Autodesk Fusion 360 part; units mm, degrees
(part 2 of 2)
sketch "Logo 2" plane through (0, 0, 64.4928) normal (0, 0, 1) x (1, 0, 0)
  line L0 (33.9049, -0.8564) -> (38.2716, 2.693)
  spline S0 degree 5 poles (38.2716, 2.693) (38.2649, 2.6875) (38.2517, 2.6763) (38.232, 2.6595) (38.206, 2.6368) (38.1742, 2.6081) (38.1429, 2.579) (38.1122, 2.5495) (38.082, 2.5196) (38.0525, 2.4893) (38.0235, 2.4586) (37.9952, 2.4275) (37.9674, 2.396) (37.9403, 2.3641) (37.9138, 2.3318) (37.8879, 2.2991) (37.8627, 2.266) (37.8381, 2.2325) (37.8142, 2.1986) (37.791, 2.1644) (37.7684, 2.1298) (37.7464, 2.0948) (37.7252, 2.0595) (37.7046, 2.0238) (37.6847, 1.9877) (37.6655, 1.9513) (37.6469, 1.9145) (37.6291, 1.8774) (37.6119, 1.8399) (37.5955, 1.8021) (37.5797, 1.764) (37.5646, 1.7256) (37.5502, 1.6868) (37.5365, 1.6478) (37.5236, 1.6084) (37.5113, 1.5687) (37.4997, 1.5288) (37.4888, 1.4885) (37.4786, 1.448) (37.4691, 1.4072) (37.4603, 1.3662) (37.4521, 1.3249) (37.4447, 1.2834) (37.4379, 1.2416) (37.4318, 1.1996) (37.4264, 1.1573) (37.4216, 1.1148) (37.4175, 1.0721) (37.414, 1.0292) (37.4112, 0.9861) (37.409, 0.9428) (37.4075, 0.8993) (37.4066, 0.8556) (37.4064, 0.8117) (37.4068, 0.7676) (37.4078, 0.7234) (37.4094, 0.6789) (37.4116, 0.6344) (37.4144, 0.5896) (37.4178, 0.5447) (37.4218, 0.4997) (37.4264, 0.4545) (37.4316, 0.4092) (37.4373, 0.3637) (37.4436, 0.3181) (37.4505, 0.2723) (37.4579, 0.2264) (37.4658, 0.1804) (37.4743, 0.1343) (37.4833, 0.088) (37.4929, 0.0416) (37.503, -0.0049) (37.5135, -0.0515) (37.5246, -0.0982) (37.5363, -0.145) (37.5484, -0.1919) (37.561, -0.239) (37.574, -0.2861) (37.5876, -0.3333) (37.6017, -0.3806) (37.6162, -0.428) (37.6312, -0.4755) (37.6467, -0.5231) (37.6626, -0.5708) (37.6789, -0.6186) (37.6957, -0.6665) (37.7129, -0.7144) (37.7306, -0.7625) (37.7487, -0.8106) (37.7672, -0.8588) (37.7861, -0.907) (37.8055, -0.9554) (37.8253, -1.0038) (37.8455, -1.0523) (37.8661, -1.1008) (37.8871, -1.1495) (37.9085, -1.1982) (37.9303, -1.247) (37.9524, -1.2958) (37.975, -1.3447) (37.9979, -1.3937) (38.0213, -1.4428) (38.045, -1.4919) (38.069, -1.5411) (38.0934, -1.5903) (38.1182, -1.6396) (38.1433, -1.689) (38.1688, -1.7384) (38.1946, -1.7879) (38.2208, -1.8375) (38.2474, -1.8871) (38.2742, -1.9368) (38.3014, -1.9865) (38.329, -2.0363) (38.3569, -2.0862) (38.3851, -2.1361) (38.4136, -2.186) (38.4425, -2.2361) (38.4716, -2.2861) (38.5011, -2.3363) (38.531, -2.3864) (38.5611, -2.4367) (38.5915, -2.487) (38.6223, -2.5373) (38.6533, -2.5877) (38.6847, -2.6382) (38.7163, -2.6887) (38.7482, -2.7392) (38.7805, -2.7898) (38.813, -2.8405) (38.8458, -2.8912) (38.8789, -2.942) (38.9122, -2.9929) (38.9459, -3.0437) (38.9798, -3.0947) (39.014, -3.1456) (39.0485, -3.1966) (39.0833, -3.2476) (39.1184, -3.2987) (39.1538, -3.3498) (39.1894, -3.401) (39.2252, -3.4523) (39.2613, -3.5036) (39.2976, -3.555) (39.3341, -3.6066) (39.3709, -3.6581) (39.408, -3.7096) (39.4454, -3.7612) (39.4832, -3.8126) (39.5213, -3.864) (39.5597, -3.9155) (39.5984, -3.967) (39.6371, -4.0186) (39.676, -4.0705) (39.7148, -4.1226) (39.7536, -4.175) (39.7926, -4.2276) (39.8318, -4.2802) (39.8714, -4.3327) (39.9118, -4.3848) (39.9529, -4.4363) (39.9951, -4.4872) (40.0382, -4.5373) (40.0822, -4.5866) (40.1268, -4.6353) (40.1719, -4.6834) (40.2173, -4.7312) (40.2625, -4.7788) (40.3076, -4.8263) (40.3524, -4.8736) (40.3969, -4.921) (40.4413, -4.9681) (40.4855, -5.0152) (40.5297, -5.0619) (40.574, -5.1084) (40.6185, -5.1546) (40.663, -5.2004) (40.7076, -5.2459) (40.7523, -5.2911) (40.7971, -5.3361) (40.8417, -5.3808) (40.8864, -5.4253) (40.931, -5.4695) (40.9756, -5.5135) (41.0201, -5.5572) (41.0647, -5.6006) (41.1093, -5.6438) (41.1539, -5.6867) (41.1986, -5.7293) (41.2432, -5.7716) (41.2879, -5.8136) (41.3326, -5.8554) (41.3773, -5.8968) (41.422, -5.938) (41.4667, -5.9789) (41.5114, -6.0195) (41.5561, -6.0598) (41.6008, -6.0997) (41.6455, -6.1394) (41.6903, -6.1788) (41.735, -6.2179) (41.7798, -6.2567) (41.8245, -6.2951) (41.8693, -6.3333) (41.9141, -6.3711) (41.9589, -6.4087) (42.0037, -6.4459) (42.0485, -6.4827) (42.0933, -6.5193) (42.1381, -6.5555) (42.183, -6.5914) (42.2278, -6.6269) (42.2727, -6.6621) (42.3176, -6.6969) (42.3624, -6.7315) (42.4073, -6.7656) (42.4522, -6.7994) (42.4971, -6.8329) (42.5421, -6.866) (42.587, -6.8988) (42.6319, -6.9312) (42.6769, -6.9632) (42.7218, -6.9948) (42.7668, -7.0261) (42.8118, -7.057) (42.8567, -7.0875) (42.9017, -7.1176) (42.9467, -7.1473) (42.9917, -7.1766) (43.0367, -7.2056) (43.0817, -7.2341) (43.1267, -7.2623) (43.1718, -7.29) (43.2168, -7.3173) (43.2619, -7.3442) (43.3069, -7.3707) (43.352, -7.3967) (43.397, -7.4223) (43.4421, -7.4475) (43.4872, -7.4722) (43.5322, -7.4965) (43.5773, -7.5203) (43.6223, -7.5437) (43.6674, -7.5666) (43.7125, -7.5891) (43.7575, -7.6111) (43.8026, -7.6326) (43.8477, -7.6536) (43.8927, -7.6741) (43.9378, -7.6942) (43.9828, -7.7138) (44.0279, -7.7328) (44.0729, -7.7514) (44.1179, -7.7695) (44.1629, -7.787) (44.2079, -7.804) (44.2528, -7.8205) (44.2978, -7.8364) (44.3427, -7.8518) (44.3876, -7.8666) (44.4325, -7.8809) (44.4774, -7.8946) (44.5222, -7.9078) (44.567, -7.9204) (44.6118, -7.9325) (44.6566, -7.9439) (44.7013, -7.9548) (44.7459, -7.965) (44.7905, -7.9747) (44.8351, -7.9838) (44.8796, -7.9922) (44.9241, -8.0001) (44.9685, -8.0073) (45.0129, -8.0139) (45.0572, -8.0198) (45.1014, -8.0251) (45.1455, -8.0298) (45.1896, -8.0338) (45.2336, -8.0372) (45.2775, -8.04) (45.3213, -8.042) (45.365, -8.0434) (45.4086, -8.0442) (45.4521, -8.0443) (45.4955, -8.0437) (45.5388, -8.0424) (45.582, -8.0404) (45.6251, -8.0377) (45.668, -8.0343) (45.7108, -8.0303) (45.7534, -8.0256) (45.7959, -8.0201) (45.8383, -8.014) (45.8805, -8.0071) (45.9226, -7.9996) (45.9645, -7.9914) (46.0062, -7.9824) (46.0477, -7.9728) (46.089, -7.9624) (46.1302, -7.9514) (46.1712, -7.9397) (46.2119, -7.9273) (46.2525, -7.9142) (46.2929, -7.9004) (46.333, -7.8859) (46.373, -7.8707) (46.4127, -7.8549) (46.4522, -7.8383) (46.4915, -7.8211) (46.5305, -7.8032) (46.5693, -7.7847) (46.6079, -7.7655) (46.6462, -7.7456) (46.6843, -7.7251) (46.7221, -7.7039) (46.7597, -7.6821) (46.797, -7.6597) (46.8341, -7.6366) (46.8709, -7.6129) (46.9074, -7.5886) (46.9437, -7.5636) (46.9726, -7.5432) (46.9941, -7.5276) (47.0084, -7.5171) (47.0155, -7.5118) knots 0 0 0 0 0 0 0.003125 0.00625 0.009375 0.0125 0.015625 0.01875 0.021875 0.025 0.028125 0.03125 0.034375 0.0375 0.040625 0.04375 0.046875 0.05 0.053125 0.05625 0.059375 0.0625 0.065625 0.06875 0.071875 0.075 0.078125 0.08125 0.084375 0.0875 0.090625 0.09375 0.096875 0.1 0.103125 0.10625 0.109375 0.1125 0.115625 0.11875 0.121875 0.125 0.128125 0.13125 0.134375 0.1375 0.140625 0.14375 0.146875 0.15 0.153125 0.15625 0.159375 0.1625 0.165625 0.16875 0.171875 0.175 0.178125 0.18125 0.184375 0.1875 0.190625 0.19375 0.196875 0.2 0.203125 0.20625 0.209375 0.2125 0.215625 0.21875 0.221875 0.225 0.228125 0.23125 0.234375 0.2375 0.240625 0.24375 0.246875 0.25 0.253125 0.25625 0.259375 0.2625 0.265625 0.26875 0.271875 0.275 0.278125 0.28125 0.284375 0.2875 0.290625 0.29375 0.296875 0.3 0.303125 0.30625 0.309375 0.3125 0.315625 0.31875 0.321875 0.325 0.328125 0.33125 0.334375 0.3375 0.340625 0.34375 0.346875 0.35 0.353125 0.35625 0.359375 0.3625 0.365625 0.36875 0.371875 0.375 0.378125 0.38125 0.384375 0.3875 0.390625 0.39375 0.396875 0.4 0.403125 0.40625 0.409375 0.4125 0.415625 0.41875 0.421875 0.425 0.428125 0.43125 0.434375 0.4375 0.440625 0.44375 0.446875 0.45 0.453125 0.45625 0.459375 0.4625 0.465625 0.46875 0.471875 0.475 0.478125 0.48125 0.484375 0.4875 0.490625 0.49375 0.496875 0.5 0.503125 0.50625 0.509375 0.5125 0.515625 0.51875 0.521875 0.525 0.528125 0.53125 0.534375 0.5375 0.540625 0.54375 0.546875 0.55 0.553125 0.55625 0.559375 0.5625 0.565625 0.56875 0.571875 0.575 0.578125 0.58125 0.584375 0.5875 0.590625 0.59375 0.596875 0.6 0.603125 0.60625 0.609375 0.6125 0.615625 0.61875 0.621875 0.625 0.628125 0.63125 0.634375 0.6375 0.640625 0.64375 0.646875 0.65 0.653125 0.65625 0.659375 0.6625 0.665625 0.66875 0.671875 0.675 0.678125 0.68125 0.684375 0.6875 0.690625 0.69375 0.696875 0.7 0.703125 0.70625 0.709375 0.7125 0.715625 0.71875 0.721875 0.725 0.728125 0.73125 0.734375 0.7375 0.740625 0.74375 0.746875 0.75 0.753125 0.75625 0.759375 0.7625 0.765625 0.76875 0.771875 0.775 0.778125 0.78125 0.784375 0.7875 0.790625 0.79375 0.796875 0.8 0.803125 0.80625 0.809375 0.8125 0.815625 0.81875 0.821875 0.825 0.828125 0.83125 0.834375 0.8375 0.840625 0.84375 0.846875 0.85 0.853125 0.85625 0.859375 0.8625 0.865625 0.86875 0.871875 0.875 0.878125 0.88125 0.884375 0.8875 0.890625 0.89375 0.896875 0.9 0.903125 0.90625 0.909375 0.9125 0.915625 0.91875 0.921875 0.925 0.928125 0.93125 0.934375 0.9375 0.940625 0.94375 0.946875 0.95 0.953125 0.95625 0.959375 0.9625 0.965625 0.96875 0.971875 0.975 0.978125 0.98125 0.984375 0.9875 0.990625 0.99375 0.996875 1 1 1 1 1 1
  line L1 (47.0155, -7.5118) -> (42.7359, -11.0673)
  spline S1 degree 5 poles (42.7359, -11.0673) (42.7287, -11.0714) (42.7142, -11.0797) (42.6924, -11.0918) (42.6632, -11.1077) (42.6265, -11.127) (42.5896, -11.1457) (42.5526, -11.1639) (42.5153, -11.1815) (42.4779, -11.1985) (42.4403, -11.215) (42.4025, -11.2309) (42.3646, -11.2463) (42.3264, -11.261) (42.2881, -11.2752) (42.2497, -11.2888) (42.211, -11.3018) (42.1722, -11.3143) (42.1332, -11.3261) (42.0941, -11.3374) (42.0549, -11.348) (42.0155, -11.3581) (41.9759, -11.3676) (41.9363, -11.3765) (41.8965, -11.3848) (41.8565, -11.3924) (41.8164, -11.3995) (41.7762, -11.406) (41.7359, -11.4119) (41.6955, -11.4171) (41.655, -11.4218) (41.6143, -11.4259) (41.5735, -11.4294) (41.5327, -11.4324) (41.4917, -11.4347) (41.4507, -11.4364) (41.4095, -11.4376) (41.3683, -11.4381) (41.327, -11.4381) (41.2856, -11.4375) (41.2442, -11.4364) (41.2027, -11.4346) (41.1611, -11.4323) (41.1194, -11.4294) (41.0777, -11.4259) (41.0359, -11.4218) (40.9941, -11.4172) (40.9523, -11.4121) (40.9104, -11.4064) (40.8684, -11.4001) (40.8264, -11.3933) (40.7844, -11.386) (40.7423, -11.3781) (40.7002, -11.3697) (40.658, -11.3608) (40.6159, -11.3513) (40.5737, -11.3413) (40.5315, -11.3308) (40.4893, -11.3198) (40.447, -11.3083) (40.4048, -11.2962) (40.3625, -11.2837) (40.3202, -11.2707) (40.2779, -11.2572) (40.2356, -11.2432) (40.1933, -11.2287) (40.1509, -11.2138) (40.1086, -11.1984) (40.0663, -11.1825) (40.024, -11.1661) (39.9816, -11.1493) (39.9393, -11.1321) (39.8969, -11.1144) (39.8546, -11.0962) (39.8123, -11.0776) (39.77, -11.0586) (39.7277, -11.0391) (39.6854, -11.0192) (39.6431, -10.9988) (39.6008, -10.9781) (39.5586, -10.9569) (39.5163, -10.9353) (39.474, -10.9133) (39.4318, -10.8909) (39.3895, -10.8682) (39.3473, -10.845) (39.3051, -10.8214) (39.2629, -10.7974) (39.2208, -10.773) (39.1786, -10.7483) (39.1365, -10.7231) (39.0944, -10.6976) (39.0523, -10.6717) (39.0102, -10.6455) (38.9681, -10.6189) (38.926, -10.5919) (38.884, -10.5646) (38.8419, -10.537) (38.7999, -10.509) (38.7579, -10.4806) (38.7159, -10.4519) (38.674, -10.4228) (38.632, -10.3934) (38.5901, -10.3636) (38.5482, -10.3335) (38.5064, -10.3031) (38.4645, -10.2723) (38.4227, -10.2412) (38.3809, -10.2098) (38.3391, -10.1781) (38.2973, -10.1461) (38.2555, -10.1138) (38.2137, -10.0811) (38.172, -10.0482) (38.1303, -10.0149) (38.0886, -9.9813) (38.0469, -9.9475) (38.0052, -9.9133) (37.9636, -9.8788) (37.922, -9.8441) (37.8804, -9.809) (37.8388, -9.7737) (37.7972, -9.738) (37.7557, -9.7021) (37.7141, -9.6659) (37.6726, -9.6294) (37.6311, -9.5926) (37.5896, -9.5556) (37.5482, -9.5183) (37.5067, -9.4807) (37.4653, -9.4429) (37.4239, -9.4048) (37.3825, -9.3664) (37.3412, -9.3278) (37.2998, -9.2889) (37.2584, -9.2497) (37.2171, -9.2102) (37.1758, -9.1705) (37.1345, -9.1305) (37.0932, -9.0903) (37.052, -9.0499) (37.0108, -9.0092) (36.9697, -8.9684) (36.9286, -8.9273) (36.8874, -8.8859) (36.8462, -8.8442) (36.8049, -8.8021) (36.7636, -8.7598) (36.7222, -8.7172) (36.6809, -8.6743) (36.6398, -8.6314) (36.5988, -8.5884) (36.558, -8.5454) (36.5174, -8.5023) (36.4769, -8.4591) (36.4363, -8.4155) (36.3954, -8.3714) (36.3541, -8.3266) (36.3122, -8.281) (36.2698, -8.2344) (36.2268, -8.1871) (36.1835, -8.1391) (36.1399, -8.0906) (36.0964, -8.0419) (36.0531, -7.9933) (36.0102, -7.9448) (35.9677, -7.8966) (35.9257, -7.8486) (35.8842, -7.8009) (35.843, -7.7533) (35.802, -7.7057) (35.7613, -7.6581) (35.7207, -7.6104) (35.6803, -7.5626) (35.6401, -7.5146) (35.6, -7.4667) (35.5602, -7.4187) (35.5206, -7.3708) (35.4814, -7.3229) (35.4424, -7.2751) (35.4037, -7.2273) (35.3653, -7.1796) (35.3272, -7.1319) (35.2893, -7.0842) (35.2517, -7.0364) (35.2144, -6.9887) (35.1773, -6.9409) (35.1404, -6.8932) (35.1039, -6.8454) (35.0676, -6.7977) (35.0316, -6.75) (34.9958, -6.7023) (34.9604, -6.6546) (34.9252, -6.607) (34.8904, -6.5593) (34.8558, -6.5117) (34.8215, -6.464) (34.7875, -6.4164) (34.7538, -6.3688) (34.7204, -6.3212) (34.6873, -6.2736) (34.6545, -6.226) (34.622, -6.1784) (34.5898, -6.1308) (34.5579, -6.0833) (34.5263, -6.0357) (34.495, -5.9882) (34.4641, -5.9407) (34.4335, -5.8931) (34.4032, -5.8456) (34.3732, -5.7981) (34.3435, -5.7507) (34.3142, -5.7032) (34.2852, -5.6558) (34.2565, -5.6083) (34.2282, -5.5609) (34.2002, -5.5135) (34.1726, -5.4661) (34.1453, -5.4188) (34.1184, -5.3714) (34.0918, -5.324) (34.0656, -5.2767) (34.0397, -5.2294) (34.0142, -5.1821) (33.9891, -5.1348) (33.9643, -5.0875) (33.9399, -5.0403) (33.9159, -4.9931) (33.8922, -4.9458) (33.869, -4.8987) (33.8461, -4.8515) (33.8236, -4.8043) (33.8015, -4.7572) (33.7798, -4.7101) (33.7585, -4.663) (33.7377, -4.616) (33.7172, -4.5689) (33.6971, -4.5219) (33.6775, -4.475) (33.6583, -4.428) (33.6395, -4.3811) (33.6211, -4.3342) (33.6031, -4.2873) (33.5856, -4.2405) (33.5686, -4.1937) (33.552, -4.1469) (33.5358, -4.1002) (33.5202, -4.0535) (33.5049, -4.0069) (33.4901, -3.9603) (33.4758, -3.9137) (33.462, -3.8672) (33.4486, -3.8207) (33.4357, -3.7743) (33.4232, -3.7279) (33.4113, -3.6816) (33.3999, -3.6353) (33.389, -3.5891) (33.3785, -3.5429) (33.3686, -3.4968) (33.3593, -3.4508) (33.3504, -3.4048) (33.342, -3.3589) (33.3342, -3.313) (33.3269, -3.2673) (33.3201, -3.2216) (33.3139, -3.1759) (33.3082, -3.1304) (33.303, -3.0849) (33.2984, -3.0395) (33.2944, -2.9942) (33.2909, -2.949) (33.288, -2.9039) (33.2857, -2.8589) (33.2839, -2.814) (33.2827, -2.7692) (33.2821, -2.7245) (33.282, -2.68) (33.2825, -2.6355) (33.2836, -2.5912) (33.2853, -2.547) (33.2877, -2.5029) (33.2906, -2.4589) (33.2941, -2.4151) (33.2982, -2.3714) (33.303, -2.3279) (33.3083, -2.2845) (33.3143, -2.2413) (33.3209, -2.1982) (33.328, -2.1553) (33.3358, -2.1126) (33.3442, -2.07) (33.3532, -2.0276) (33.3628, -1.9854) (33.3731, -1.9434) (33.3839, -1.9015) (33.3954, -1.8599) (33.4075, -1.8184) (33.4203, -1.7772) (33.4336, -1.7361) (33.4476, -1.6953) (33.4621, -1.6547) (33.4773, -1.6143) (33.4931, -1.5741) (33.5094, -1.5341) (33.5264, -1.4943) (33.544, -1.4548) (33.5622, -1.4156) (33.581, -1.3765) (33.6004, -1.3377) (33.6204, -1.2992) (33.6409, -1.2608) (33.6621, -1.2228) (33.6838, -1.185) (33.7061, -1.1474) (33.729, -1.1101) (33.7524, -1.0731) (33.7764, -1.0363) (33.801, -0.9998) (33.8261, -0.9635) (33.8518, -0.9275) (33.8728, -0.8989) (33.8887, -0.8776) (33.8995, -0.8635) (33.9049, -0.8564) knots 0 0 0 0 0 0 0.003125 0.00625 0.009375 0.0125 0.015625 0.01875 0.021875 0.025 0.028125 0.03125 0.034375 0.0375 0.040625 0.04375 0.046875 0.05 0.053125 0.05625 0.059375 0.0625 0.065625 0.06875 0.071875 0.075 0.078125 0.08125 0.084375 0.0875 0.090625 0.09375 0.096875 0.1 0.103125 0.10625 0.109375 0.1125 0.115625 0.11875 0.121875 0.125 0.128125 0.13125 0.134375 0.1375 0.140625 0.14375 0.146875 0.15 0.153125 0.15625 0.159375 0.1625 0.165625 0.16875 0.171875 0.175 0.178125 0.18125 0.184375 0.1875 0.190625 0.19375 0.196875 0.2 0.203125 0.20625 0.209375 0.2125 0.215625 0.21875 0.221875 0.225 0.228125 0.23125 0.234375 0.2375 0.240625 0.24375 0.246875 0.25 0.253125 0.25625 0.259375 0.2625 0.265625 0.26875 0.271875 0.275 0.278125 0.28125 0.284375 0.2875 0.290625 0.29375 0.296875 0.3 0.303125 0.30625 0.309375 0.3125 0.315625 0.31875 0.321875 0.325 0.328125 0.33125 0.334375 0.3375 0.340625 0.34375 0.346875 0.35 0.353125 0.35625 0.359375 0.3625 0.365625 0.36875 0.371875 0.375 0.378125 0.38125 0.384375 0.3875 0.390625 0.39375 0.396875 0.4 0.403125 0.40625 0.409375 0.4125 0.415625 0.41875 0.421875 0.425 0.428125 0.43125 0.434375 0.4375 0.440625 0.44375 0.446875 0.45 0.453125 0.45625 0.459375 0.4625 0.465625 0.46875 0.471875 0.475 0.478125 0.48125 0.484375 0.4875 0.490625 0.49375 0.496875 0.5 0.503125 0.50625 0.509375 0.5125 0.515625 0.51875 0.521875 0.525 0.528125 0.53125 0.534375 0.5375 0.540625 0.54375 0.546875 0.55 0.553125 0.55625 0.559375 0.5625 0.565625 0.56875 0.571875 0.575 0.578125 0.58125 0.584375 0.5875 0.590625 0.59375 0.596875 0.6 0.603125 0.60625 0.609375 0.6125 0.615625 0.61875 0.621875 0.625 0.628125 0.63125 0.634375 0.6375 0.640625 0.64375 0.646875 0.65 0.653125 0.65625 0.659375 0.6625 0.665625 0.66875 0.671875 0.675 0.678125 0.68125 0.684375 0.6875 0.690625 0.69375 0.696875 0.7 0.703125 0.70625 0.709375 0.7125 0.715625 0.71875 0.721875 0.725 0.728125 0.73125 0.734375 0.7375 0.740625 0.74375 0.746875 0.75 0.753125 0.75625 0.759375 0.7625 0.765625 0.76875 0.771875 0.775 0.778125 0.78125 0.784375 0.7875 0.790625 0.79375 0.796875 0.8 0.803125 0.80625 0.809375 0.8125 0.815625 0.81875 0.821875 0.825 0.828125 0.83125 0.834375 0.8375 0.840625 0.84375 0.846875 0.85 0.853125 0.85625 0.859375 0.8625 0.865625 0.86875 0.871875 0.875 0.878125 0.88125 0.884375 0.8875 0.890625 0.89375 0.896875 0.9 0.903125 0.90625 0.909375 0.9125 0.915625 0.91875 0.921875 0.925 0.928125 0.93125 0.934375 0.9375 0.940625 0.94375 0.946875 0.95 0.953125 0.95625 0.959375 0.9625 0.965625 0.96875 0.971875 0.975 0.978125 0.98125 0.984375 0.9875 0.990625 0.99375 0.996875 1 1 1 1 1 1
  point P0 (38.1304, 2.5669)
  point P1 (38.0018, 2.4346)
  point P2 (37.8857, 2.2959)
  point P3 (37.7822, 2.1508)
  point P4 (37.6913, 1.9995)
  point P5 (37.613, 1.8418)
  point P6 (37.5472, 1.6778)
  point P7 (37.494, 1.5074)
  point P8 (37.4534, 1.3307)
  point P9 (37.4254, 1.1477)
  point P10 (37.4099, 0.9583)
  point P11 (37.407, 0.7626)
  point P12 (37.4167, 0.5606)
  point P13 (37.439, 0.3523)
  point P14 (37.4738, 0.1376)
  point P15 (37.5212, -0.0834)
  point P16 (37.5812, -0.3108)
  point P17 (37.6538, -0.5444)
  point P18 (37.7389, -0.7845)
  point P19 (37.8366, -1.0308)
  point P20 (37.9469, -1.2835)
  point P21 (38.0698, -1.5425)
  point P22 (38.2052, -1.8078)
  point P23 (38.3532, -2.0795)
  point P24 (38.5138, -2.3575)
  point P25 (38.687, -2.6418)
  point P26 (38.8727, -2.9325)
  point P27 (39.071, -3.2295)
  point P28 (39.2819, -3.5328)
  point P29 (39.5054, -3.8425)
  point P30 (39.7414, -4.1585)
  point P31 (39.9901, -4.4808)
  point P32 (40.2664, -4.7829)
  point P33 (40.539, -5.0716)
  point P34 (40.808, -5.347)
  point P35 (41.0733, -5.6089)
  point P36 (41.335, -5.8575)
  point P37 (41.593, -6.0927)
  point P38 (41.8473, -6.3145)
  point P39 (42.098, -6.523)
  point P40 (42.345, -6.718)
  point P41 (42.5884, -6.8997)
  point P42 (42.8281, -7.068)
  point P43 (43.0641, -7.2229)
  point P44 (43.2965, -7.3645)
  point P45 (43.5252, -7.4926)
  point P46 (43.7502, -7.6074)
  point P47 (43.9716, -7.7088)
  point P48 (44.1893, -7.7969)
  point P49 (44.4033, -7.8715)
  point P50 (44.6137, -7.9328)
  point P51 (44.8204, -7.9807)
  point P52 (45.0235, -8.0152)
  point P53 (45.2229, -8.0363)
  point P54 (45.4186, -8.0441)
  point P55 (45.6107, -8.0385)
  point P56 (45.7991, -8.0195)
  point P57 (45.9839, -7.9871)
  point P58 (46.165, -7.9413)
  point P59 (46.3424, -7.8822)
  point P60 (46.5162, -7.8097)
  point P61 (46.6863, -7.7238)
  point P62 (46.8527, -7.6245)
  point P63 (42.5754, -11.1526)
  point P64 (42.4123, -11.2267)
  point P65 (42.2466, -11.2897)
  point P66 (42.0782, -11.3416)
  point P67 (41.9073, -11.3824)
  point P68 (41.7338, -11.412)
  point P69 (41.5577, -11.4305)
  point P70 (41.3789, -11.4379)
  point P71 (41.1976, -11.4342)
  point P72 (41.0136, -11.4193)
  point P73 (40.8271, -11.3933)
  point P74 (40.6379, -11.3562)
  point P75 (40.4462, -11.3079)
  point P76 (40.2518, -11.2485)
  point P77 (40.0549, -11.178)
  point P78 (39.8553, -11.0964)
  point P79 (39.6532, -11.0036)
  point P80 (39.4484, -10.8997)
  point P81 (39.241, -10.7847)
  point P82 (39.0311, -10.6585)
  point P83 (38.8185, -10.5213)
  point P84 (38.6033, -10.3729)
  point P85 (38.3856, -10.2133)
  point P86 (38.1652, -10.0427)
  point P87 (37.9422, -9.8609)
  point P88 (37.7166, -9.668)
  point P89 (37.4884, -9.4639)
  point P90 (37.2576, -9.2488)
  point P91 (37.0243, -9.0225)
  point P92 (36.7883, -8.7851)
  point P93 (36.5497, -8.5365)
  point P94 (36.3085, -8.2768)
  point P95 (36.0398, -7.9782)
  point P96 (35.7835, -7.684)
  point P97 (35.5398, -7.394)
  point P98 (35.3085, -7.1083)
  point P99 (35.0898, -6.8269)
  point P100 (34.8835, -6.5498)
  point P101 (34.6898, -6.2771)
  point P102 (34.5085, -6.0086)
  point P103 (34.3397, -5.7444)
  point P104 (34.1834, -5.4846)
  point P105 (34.0396, -5.229)
  point P106 (33.9083, -4.9778)
  point P107 (33.7894, -4.7308)
  point P108 (33.6831, -4.4882)
  point P109 (33.5892, -4.2498)
  point P110 (33.5079, -4.0158)
  point P111 (33.439, -3.786)
  point P112 (33.3826, -3.5606)
  point P113 (33.3388, -3.3395)
  point P114 (33.3074, -3.1227)
  point P115 (33.2885, -2.9101)
  point P116 (33.2821, -2.7019)
  point P117 (33.2881, -2.498)
  point P118 (33.3067, -2.2984)
  point P119 (33.3378, -2.1031)
  point P120 (33.3813, -1.9121)
  point P121 (33.4374, -1.7254)
  point P122 (33.5059, -1.543)
  point P123 (33.5869, -1.3649)
  point P124 (33.6804, -1.1911)
  point P125 (33.7864, -1.0216)
  constraint coincident S0.end L1.start
extrude "Logo 2 (1)" add sketch "Logo 2" along normal mid plane 2.5
ref_plane "WorkPlane18" through (0, 0, 64.4928) normal (0, 0, 1) x (1, 0, 0)
sketch "Logo 3" plane through (0, 0, 64.4928) normal (0, 0, 1) x (1, 0, 0)
  line L0 (45.1668, -2.6883) -> (45.244, -5.1829)
  line L1 (45.244, -5.1829) -> (42.9606, -4.701)
  line L2 (42.9606, -4.701) -> (40.5999, -1.7246)
  line L3 (40.5999, -1.7246) -> (40.5226, 0.77)
  line L4 (40.5226, 0.77) -> (42.8061, 0.2882)
  line L5 (42.8061, 0.2882) -> (45.1668, -2.6883)
  dimension "d174" = 45.1668
  dimension "d175" = 2.6883
  dimension "d176" = 45.244
  dimension "d177" = 5.1829
  dimension "d178" = 42.9606
  dimension "d179" = 4.701
  dimension "d180" = 40.5999
  dimension "d181" = 1.7246
  dimension "d182" = 40.5226
  dimension "d183" = 0.77
  dimension "d184" = 42.8061
  dimension "d185" = 0.2882
  measures "d174" horizontal distance of origin L0.start
  measures "d175" vertical distance of origin L0.start
  measures "d176" horizontal distance of origin L0.end
  measures "d177" vertical distance of origin L0.end
  measures "d178" horizontal distance of origin L1.end
  measures "d179" vertical distance of origin L1.end
  measures "d180" horizontal distance of origin L2.end
  measures "d181" vertical distance of origin L2.end
  measures "d182" horizontal distance of origin L3.end
  measures "d183" vertical distance of origin L3.end
  measures "d184" horizontal distance of origin L4.end
  measures "d185" vertical distance of origin L4.end
extrude "Logo 3 (1)" add sketch "Logo 3" along normal mid plane 2.5
named bodies: "Servo Block native"
